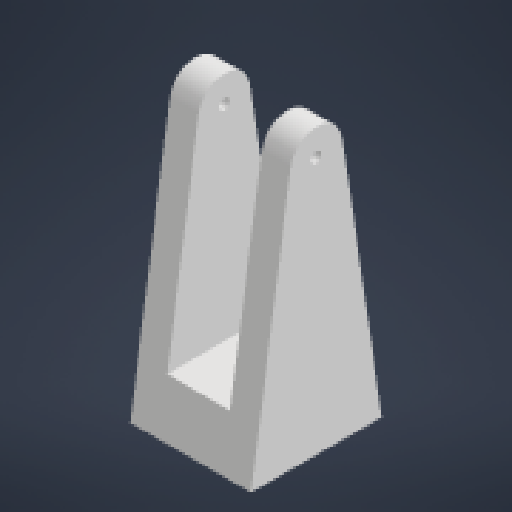
# Autodesk Inventor part: soporteBarrasBrazo
Saved by Autodesk Inventor 2027.1 (Build 311270010, 270A)
## iProperties
Created: 2026-11-02
Part Number: soporteBarrasBrazo
Material: Genérico
Document SubType Name: Modeling
Designer: MANGEL
Density: 1 g/cm^3
Appearance: Valor por defecto
Author: MANGEL
Autodesk Inventor part; units mm, degrees
ref_plane "YZ Plane" through (0, 0, 0) normal (1, 0, 0) x (0, 1, 0)
ref_plane "XZ Plane" through (0, 0, 0) normal (0, 1, 0) x (-1, 0, 0)
sketch "Boceto2" plane through (0, 0, 0) normal (1, 0, 0) x (0, 1, 0)
  line L0 (-49.75, -24.85) -> (49.75, -24.85)
  line L1 (49.75, -24.85) -> (49.75, 24.85)
  line L2 (49.75, 24.85) -> (-49.75, 24.85)
  line L3 (-49.75, 24.85) -> (-49.75, -24.85)
  line L4 (-49.75, -24.85) -> (49.75, 24.85) construction
  line L5 (49.75, -24.85) -> (-49.75, 24.85) construction
  line L6 (-49.75, 24.85) -> (49.75, 9.85)
  line L7 (-49.75, -24.85) -> (49.75, -9.85)
  arc A0 (49.75, -9.85) -> (49.75, 9.85) centre (48.2651, 0) ccw
  point P0 (0, 0)
  dimension "d4" = 15
  dimension "d5" = 99.5
  dimension "d6" = 49.7
  dimension "d7" = 15
  constraints: 16 end point, 2 midpoint, 2 parallel, 2 point on circle, 2 point on line, 1 centre point, 1 horizontal, 1 perpendicular, 1 tangent
  measures "d4" distance of L1.end L6.end
  measures "d5" distance of L1.end L2.end
  measures "d6" distance of L2.end L0.start
  measures "d7" distance of L0.end L7.end
extrude "Extrusión2" add sketch "Boceto2" along normal blind 46 contours L3 L6 L1 L7 | L1 A0
sketch "Boceto3" plane through (46, 0, 0) normal (1, 0, 0) x (0, 0, -1)
  arc A0 (9.85, 49.75) -> (-9.85, 49.75) centre (0, 48.2651) ccw projected
  circle A1 centre (0, 48.2651) radius 2
  point P0 (0, 0)
  dimension "d10" = 4
  constraints: 1 centre point, 1 coincident
  measures "d10" diameter of A1
extrude "Extrusión3" cut sketch "Boceto3" against normal through all
ref_plane "Plano de trabajo1" through (0, 0, 35) normal (0, 0, 1) x (1, 0, 0)
sketch "Boceto5" plane through (0, 0, 35) normal (0, 0, 1) x (1, 0, 0)
  line L0 (35, -29.75) -> (11, -29.75)
  line L1 (11, -29.75) -> (11, 70.3763)
  line L2 (11, 70.3763) -> (35, 70.3763)
  line L3 (35, 70.3763) -> (35, -29.75)
  line L4 (0, 49.75) -> (46, 49.75) projected
  line L5 (0, -49.75) -> (46, -49.75) projected
  point P0 (0, 0)
  point P1 (23, 70.3763)
  point P2 (23, 49.75)
  dimension "d14" = 24
  dimension "d15" = 20
  constraints: 8 end point, 2 midpoint, 2 parallel, 1 horizontal, 1 perpendicular, 1 vertical alignment
  measures "d14" distance of L0.start L0.end
  measures "d15" distance between parallel lines of L5 L0
extrude "Extrusión4" cut sketch "Boceto5" against normal through all
